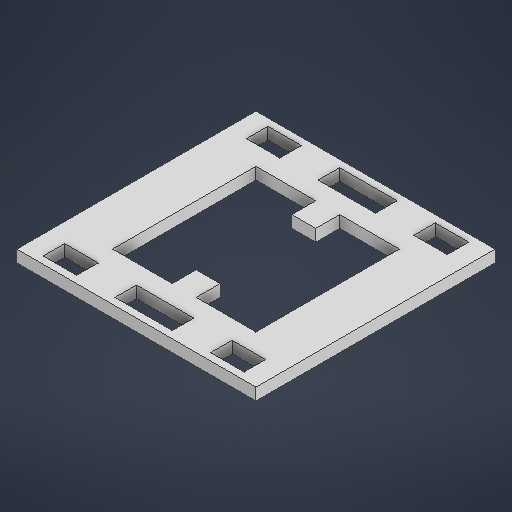
# Autodesk Inventor part: Medio
Saved by Autodesk Inventor 2025.2 (Build 292293000, 293)
## iProperties
Created: 2025-06-04
Part Number: Medio
Material: Genérico
Document SubType Name: Modeling
Designer: Niko
Density: 1 g/cm^3
Appearance: Valor por defecto
Author: Niko
Autodesk Inventor part; units mm, degrees
ref_plane "YZ Plane" through (0, 0, 0) normal (1, 0, 0) x (0, 1, 0)
ref_plane "XZ Plane" through (0, 0, 0) normal (0, 1, 0) x (-1, 0, 0)
ref_plane "XY Plane" through (0, 0, 0) normal (0, 0, 1) x (1, 0, 0)
sketch "Boceto1" plane through (0, 0, 0) normal (0, 1, 0) x (-1, 0, 0)
  line L0 (50, 50) -> (-50, 50)
  line L1 (-50, 50) -> (-50, -50)
  line L2 (-50, -50) -> (50, -50)
  line L3 (50, -50) -> (50, 50)
  line L4 (50, 30) -> (50, 50)
  line L5 (-30, 30) -> (-30, -30)
  line L6 (30, -30) -> (30, 30)
  line L7 (30, 30) -> (5, 30)
  line L8 (-5, 30) -> (-5, 20)
  line L9 (-5, 20) -> (5, 20)
  line L10 (5, 20) -> (5, 30)
  line L11 (-5, -30) -> (-5, -20)
  line L12 (-5, -20) -> (5, -20)
  line L13 (5, -20) -> (5, -30)
  line L14 (-30, -30) -> (-5, -30)
  line L15 (5, -30) -> (30, -30)
  line L16 (30, 30) -> (5, 30)
  line L17 (-5, 30) -> (-30, 30)
  line L18 (50, 50) -> (50, 45)
  line L19 (50, -50) -> (50, -47)
  line L20 (42, -47) -> (28, -47)
  line L21 (28, -47) -> (28, -38)
  line L22 (28, -38) -> (42, -38)
  line L23 (42, -38) -> (42, -47)
  line L24 (-50, -50) -> (-42, -50)
  line L25 (-42, -47) -> (-28, -47)
  line L26 (-28, -47) -> (-28, -38)
  line L27 (-28, -38) -> (-42, -38)
  line L28 (-42, -38) -> (-42, -47)
  line L29 (12, -47) -> (-12, -47)
  line L30 (-12, -47) -> (-12, -38)
  line L31 (-12, -38) -> (12, -38)
  line L32 (12, -38) -> (12, -47)
  line L33 (42, 47) -> (28, 47)
  line L34 (28, 47) -> (28, 38)
  line L35 (28, 38) -> (42, 38)
  line L36 (42, 38) -> (42, 47)
  line L37 (-42, 47) -> (-28, 47)
  line L38 (-28, 47) -> (-28, 38)
  line L39 (-28, 38) -> (-42, 38)
  line L40 (-42, 38) -> (-42, 47)
  line L41 (12, 47) -> (-12, 47)
  line L42 (-12, 47) -> (-12, 38)
  line L43 (-12, 38) -> (12, 38)
  line L44 (12, 38) -> (12, 47)
  point P0 (0, 0)
  constraints: 90 end point, 15 parallel, 6 horizontal, 6 perpendicular, 5 point on line
extrude "Extrusión2" add sketch "Boceto1" along normal blind 5
